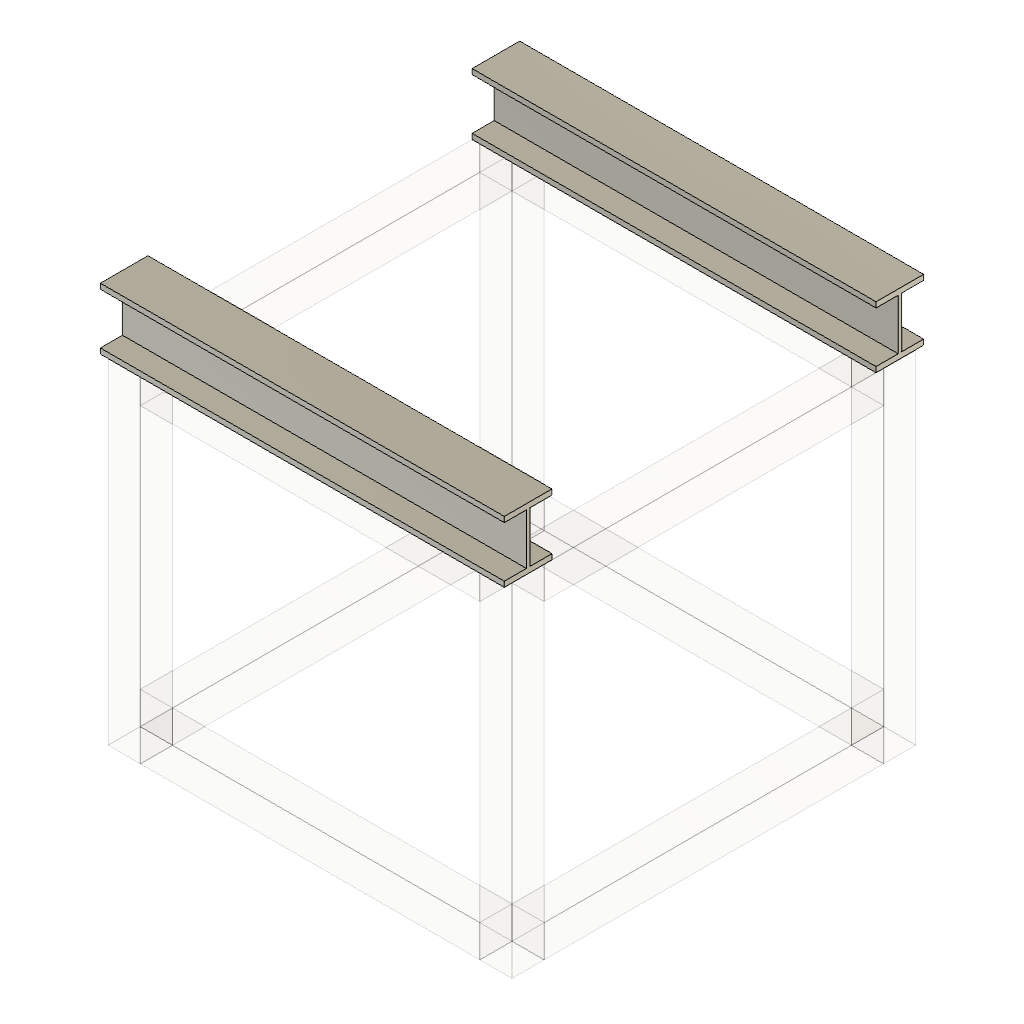
Gantry_Frame_v1 (Autodesk Fusion 360 design; units mm, degrees)
part number: 2026-11-03-13-49-15-629
part number: 2026-11-05-15-03-57-046
part number: 2026-11-05-15-06-09-851
part number: 2026-11-05-15-55-46-866
part number: 2026-11-08-21-34-18-338
Autodesk Fusion 360 part; units mm, degrees
sketch "Sketch1" plane through (0, 0, 0) normal (0, 0, 1) x (1, 0, 0) in component "post"
  line L0 (-250, -250) -> (-210, -250)
  line L1 (-210, -250) -> (-210, -210)
  line L2 (-210, -210) -> (-250, -210)
  line L3 (-250, -210) -> (-250, -250)
  dimension "d8" = 40
  dimension "d9" = 40
  dimension "d10" = 40
  dimension "d11" = 40
  dimension "d12" = 250
  dimension "d13" = 250
  constraint horizontal L0
  constraint vertical L1
  constraint horizontal L2
  constraint vertical L3
  measures "d8" distance of L0.start L0.end
  measures "d9" distance of L0.start L2.end
  measures "d10" distance of L0.start L0.end
  measures "d11" distance of L0.start L2.end
  measures "d12" vertical distance of origin L0.start
  measures "d13" horizontal distance of origin L0.start
extrude "Extrude1" add sketch "Sketch1" along normal blind 424 makes body 1 in component "post"
pattern_linear "00000000-0000-0000-0000-000000000000" [suppressed] in component "Frame"
sketch "Sketch1 (2)" plane through (0, 0, 0) normal (0, 0, 1) x (1, 0, 0) in component "Tie"
sketch "Sketch2" plane through (-210, 0, 0) normal (1, 0, 0) x (0, 1, 0) in component "Tie"
  line L0 (-250, 0) -> (-210, 0)
  line L1 (-210, 0) -> (-210, 424)
  line L2 (-210, 424) -> (-250, 424)
  line L3 (-250, 424) -> (-250, 0)
  line L4 (-250, 0) -> (-210, 0)
  line L5 (-210, 0) -> (-210, 424)
  line L6 (-210, 424) -> (-250, 424)
  line L7 (-250, 424) -> (-250, 0)
  line L8 (-250, 424) -> (-210, 424)
  line L9 (-210, 424) -> (-210, 384)
  line L10 (-210, 384) -> (-250, 384)
  line L11 (-250, 384) -> (-250, 424)
  dimension "d20" = 40
  constraint horizontal L8
  constraint vertical L9
  constraint horizontal L10
  constraint vertical L11
  constraint coincident L5 L9.end
  constraint coincident L2.end L3.start
  measures "d20" distance of L2.end L10.end
extrude "Extrude1'" add sketch "Sketch2" along normal blind 420 separate body contours L1 L2 L3 L5 L6 L7 L8 L9 L10 L11 makes body 2 in component "Tie"
pattern_circular "C-Pattern1" count 4 over 360 about axis through (0, 0, 1.75) along (0, 0, 1) of bodies 2 makes body 3 at (250, -70, 410.6667) makes body 4 at (70, 250, 410.6667) makes body 5 at (-250, 70, 410.6667) in component "Tie"
pattern_linear "00000000-0000-0000-0000-000000000000'" [suppressed] in component "Frame"
sketch "Sketch1 (3)" plane through (0, 0, 0) normal (1, 0, 0) x (0, 1, 0) in component "Rail_X"
  line L0 (259.5, 430.6) -> (200.5, 430.6)
  line L1 (200.5, 430.6) -> (200.5, 424)
  line L2 (200.5, 424) -> (259.5, 424)
  line L3 (259.5, 424) -> (259.5, 430.6)
  line L4 (259.5, 430.6) -> (200.5, 424) construction
  line L5 (200.5, 430.6) -> (259.5, 424) construction
  line L6 (232.15, 493.4) -> (227.85, 493.4)
  line L7 (227.85, 493.4) -> (227.85, 430.6)
  line L8 (227.85, 430.6) -> (232.15, 430.6)
  line L9 (232.15, 430.6) -> (232.15, 493.4)
  line L10 (232.15, 493.4) -> (227.85, 430.6) construction
  line L11 (227.85, 493.4) -> (232.15, 430.6) construction
  line L12 (259.5, 500) -> (200.5, 500)
  line L13 (200.5, 500) -> (200.5, 493.4)
  line L14 (200.5, 493.4) -> (259.5, 493.4)
  line L15 (259.5, 493.4) -> (259.5, 500)
  line L16 (259.5, 500) -> (200.5, 493.4) construction
  line L17 (200.5, 500) -> (259.5, 493.4) construction
  point P0 (230, 427.3)
  point P1 (230, 462)
  point P2 (230, 496.7)
  dimension "d40" = 59
  dimension "d41" = 6.6
  dimension "d44" = 427.3
  dimension "d45" = 230
  dimension "d46" = 4.3
  dimension "d47" = 62.8
  dimension "d48" = 34.7
  dimension "d49" = 59
  dimension "d50" = 6.6
  dimension "d51" = 34.7
  constraint horizontal L0
  constraint perpendicular L0 L1
  constraint parallel L0 L2
  constraint parallel L1 L3
  constraint coincident L4 P0
  constraint coincident L5 P0
  constraint horizontal L6
  constraint perpendicular L6 L7
  constraint parallel L6 L8
  constraint parallel L7 L9
  constraint coincident L10 P1
  constraint coincident L11 P1
  constraint vertical P0 P1
  constraint horizontal L12
  constraint perpendicular L12 L13
  constraint parallel L12 L14
  constraint parallel L13 L15
  constraint coincident L16 P2
  constraint coincident L17 P2
  constraint vertical P1 P2
  measures "d40" distance of L1.end L2.end
  measures "d41" distance of L0.end L1.end
  measures "d44" vertical distance of P0 origin
  measures "d45" horizontal distance of origin P0
  measures "d46" distance of L6.start L6.end
  measures "d47" distance of L6.start L8.end
  measures "d48" distance of P0 P1
  measures "d49" distance of L13.end L14.end
  measures "d50" distance of L12.end L13.end
  measures "d51" distance of P1 P2
extrude "Extrude1''" add sketch "Sketch1 (3)" along normal mid plane 500 separate body makes body 6 in component "Rail_X"
mirror "Mirror1" about plane through (0, 0, 0) normal (0, 1, 0) of bodies 6 makes body 7 in component "Rail_X"
component "Frame" placed x (1, 0, 0) y (0, 1, 0) z (0, 0, 1) at (0, 0, 0)
component "post" placed x (1, 0, 0) y (0, 1, 0) z (0, 0, 1) at (0, 0, 0) in component "Frame"
component "Tie" placed x (1, 0, 0) y (0, 1, 0) z (0, 0, 1) at (0, 0, 0) in component "Frame"
component "post" placed x (1, 0, 0) y (0, 1, 0) z (0, 0, 1) at (0, 460, 0) in component "Frame"
component "post" placed x (1, 0, 0) y (0, 1, 0) z (0, 0, 1) at (460, 0, 0) in component "Frame"
component "post" placed x (1, 0, 0) y (0, 1, 0) z (0, 0, 1) at (460, 460, 0) in component "Frame"
component "Rail_X" placed x (1, 0, 0) y (0, 1, 0) z (0, 0, 1) at (0, 0, 0) in component "Frame"
component "Tie" placed x (1, 0, 0) y (0, 1, 0) z (0, 0, 1) at (0, 0, -384) in component "Frame"
equation "frame_size = 500 mm"
equation "post = 40 mm"
equation "rail_length = frame_size"
equation "ib_depth = 76 mm"
equation "ib_flange_w = 59 mm"
equation "ib_flange_t = 6.6 mm"
equation "ib_web_t = 4.3 mm"
equation "d12 = frame_size / 2"
equation "d13 = frame_size / 2"
equation "d14 = rail_z"
equation "d18 = frame_size - post"
equation "d19 = -( frame_size - post )"
equation "d20 = post"
equation "d23 = frame_size - 2 * ( post )"
equation "d29 = -( rail_z - post )"
equation "web_h = ib_depth - 2 * ib_flange_t"
equation "rail_y = frame_size / 2 - post / 2"
equation "rail_z = frame_size - ib_depth"
equation "d40 = ib_flange_w"
equation "d41 = ib_flange_t"
equation "d44 = rail_z + ib_flange_t / 2"
equation "d45 = rail_y"
equation "d46 = ib_web_t"
equation "d47 = web_h"
equation "d48 = ib_flange_t / 2 + web_h / 2"
equation "d49 = ib_flange_w"
equation "d50 = ib_flange_t"
equation "d51 = web_h / 2 + ib_flange_t / 2"
equation "d52 = frame_size"
